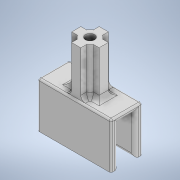
# Autodesk Inventor part: ghidaj_gaura_push_pal
Saved by Autodesk Inventor 2022.6 (Build 266554000, 554)
## iProperties
Created: 2026-01-13
Part Number: ghidaj_gaura_push_pal
Material: Generic
Document SubType Name: Modeling
Designer: Dragos Macovei
Density: 1 g/cm^3
Appearance: Default
Author: Dragos Macovei
Autodesk Inventor part; units mm, degrees
ref_plane "YZ Plane" through (0, 0, 0) normal (1, 0, 0) x (0, 1, 0)
ref_plane "XZ Plane" through (0, 0, 0) normal (0, 1, 0) x (-1, 0, 0)
ref_plane "XY Plane" through (0, 0, 0) normal (0, 0, 1) x (1, 0, 0)
sketch "Sketch4" plane through (0, 0, 0) normal (0, 1, 0) x (-1, 0, 0)
  line L0 (0, 0) -> (80, 0)
  line L1 (80, 0) -> (80, 18.2)
  line L2 (80, 18.2) -> (0, 18.2)
  line L3 (0, 18.2) -> (0, 0)
  line L4 (80, 18.2) -> (0, 0)
  line L5 (0, 18.2) -> (80, 0)
  circle A0 centre (40, 9.1) radius 5.05
  dimension "d13" = 18.2
  dimension "d14" = 80
  dimension "d15" = 10.1
  constraints: 12 end point, 2 parallel, 1 centre point, 1 horizontal, 1 midpoint, 1 perpendicular
  measures "d13" distance of L1.end L0.end
  measures "d14" distance between parallel lines of L3 L1
  measures "d15" diameter of A0
extrude "Extrusion3" add sketch "Sketch4" along normal blind 6 contours L4 A0 L5 L0 | L3 L5 A0 L4 | L5 A0 L4 L1 | L2 L4 A0 L5
sketch "Sketch5" plane through (0, 6, 0) normal (0, 1, 0) x (1, 0, 0)
  line L0 (0, 0) -> (-80, 0) projected
  line L1 (-80, 0) -> (-80, -18.2) projected
  line L2 (-80, -18.2) -> (0, -18.2) projected
  line L3 (0, -18.2) -> (0, 0) projected
  circle A0 centre (-40, -9.1) radius 5.05 projected
  line L4 (-80, 0) -> (-80, -18.2) projected
  line L5 (-80, -18.2) -> (0, -18.2)
  line L6 (0, -18.2) -> (0, -26.2)
  line L7 (0, -26.2) -> (-80, -26.2)
  line L8 (-80, -26.2) -> (-80, -18.2)
  line L9 (0, 0) -> (-80, 0) projected
  line L10 (0, 0) -> (-80, 0)
  line L11 (-80, 0) -> (-80, 8)
  line L12 (-80, 8) -> (0, 8)
  line L13 (0, 8) -> (0, 0)
  dimension "d18" = 8
  dimension "d19" = 8
  constraints: 16 end point, 4 parallel, 2 horizontal, 2 perpendicular, 1 point on line
  measures "d18" distance between parallel lines of L2 L7
  measures "d19" distance between parallel lines of L12 L0
extrude "Extrusion4" add sketch "Sketch5" against normal blind 50 contours L0 L11 L12 L13 | L6 L7 L8 L2
sketch "Sketch6" plane through (0, 6, 0) normal (0, 1, 0) x (1, 0, 0)
  line L0 (-80, 8) -> (-80, -26.2) projected
  line L1 (-80, -26.2) -> (0, -26.2) projected
  line L2 (0, -26.2) -> (0, 8) projected
  line L3 (0, 8) -> (-80, 8) projected
  circle A0 centre (-40, -9.1) radius 5.05 projected
  circle A1 centre (-40, -9.1) radius 5.05
  circle A2 centre (-40, -9.1) radius 10
  point P0 (0, 0)
  dimension "d22" = 20
  constraints: 2 centre point, 2 coincident, 1 concentric
  measures "d22" diameter of A2
extrude "Extrusion5" add sketch "Sketch6" along normal blind 50 contours A2
fillet "Fillet2" radius 4 8 edges at (0, 0, 9.1) (0, -22, 0) (0, -22, 18.2) (-80, -22, 0) (-80, 0, 9.1) (-80, -22, 18.2) (-40, -44, 18.2) (-40, -44, 0)
fillet "Fillet3" radius 2 8 edges at (-40, 6, -8) (-40, 6, 26.2) (0, -19, 26.2) (0, -19, -8) (0, 6, 9.1) (-80, 6, 9.1) (-80, -19, 26.2) (-80, -19, -8)
sketch "Sketch7" plane through (-40, 56, 9.1) normal (0, 1, 0) x (1, 0, 0)
  circle A0 centre (0, 0) radius 10 projected
  line L0 (-38, 15.1) -> (38, 15.1) projected
  line L1 (-38, -15.1) -> (-38, 15.1) projected
  line L2 (38, -15.1) -> (-38, -15.1) projected
  line L3 (38, 15.1) -> (38, -15.1) projected
  circle A1 centre (0, 0) radius 5.05 projected
  line L4 (-15, 5) -> (15, 5)
  line L5 (15, 5) -> (15, -5)
  line L6 (15, -5) -> (-15, -5)
  line L7 (-15, -5) -> (-15, 5)
  line L8 (-38, 15.1) -> (38, 15.1) projected
  line L9 (5, 15.1) -> (-5, 15.1)
  line L10 (-5, 15.1) -> (-5, -15.1)
  line L11 (-5, -15.1) -> (5, -15.1)
  line L12 (5, -15.1) -> (5, 15.1)
  point P0 (40, 9.1)
  point P1 (15, 0)
  point P2 (0, 15)
  point P3 (-15, 0)
  point P4 (0, -15)
  point P5 (5, -15.1)
  point P6 (5, -8.6603)
  point P7 (-5, -8.6603)
  point P8 (5, 8.6603)
  point P9 (-5, 15.1)
  point P10 (-5, 8.6603)
  point P11 (-8.6603, -5)
  point P12 (-8.6603, 5)
  point P13 (8.6603, 5)
  point P14 (8.6603, -5)
  dimension "d28" = 15
  dimension "d29" = 15
  dimension "d30" = 15
  dimension "d31" = 15
  dimension "d33" = 5
  dimension "d35" = 5
  dimension "d36" = 5
  dimension "d37" = 5
  constraints: 16 end point, 4 parallel, 2 horizontal, 2 midpoint, 2 perpendicular, 2 point on line
  measures "d28" distance of A0.centre point (-15, 0)
  measures "d29" distance of A0.centre point (0, -15)
  measures "d30" distance of A0.centre point (0, 15)
  measures "d31" distance of A0.centre point (15, 0)
  measures "d33" distance from line of A0.centre L12
  measures "d35" distance from line of A0.centre L10
  measures "d36" distance from line of A0.centre L6
  measures "d37" distance from line of A0.centre L4
extrude "Extrusion6" add sketch "Sketch7" against normal up to surface (50 mm away) contours A0 L4 L5 L6 | A0 L10 L0 L12 | L12 L2 L10 A0 | A0 L6 L7 L4
fillet "Fillet4" radius 5 14 edges at (-45, 6, 20.9801) (-47.0711, 6, 16.1711) (-51.8301, 6, 14.1) (-55, 6, 9.1) (-51.8301, 6, 4.1) (-47.0711, 6, 2.0289) (-45, 6, -2.7801) (-35, 6, 20.9801) (-32.9289, 6, 16.1711) (-28.1699, 6, 14.1) (-25, 6, 9.1) (-28.1699, 6, 4.1) (-32.9289, 6, 2.0289) (-35, 6, -2.7801)
equation "\"d35\" = d33"
body "Solid2"
